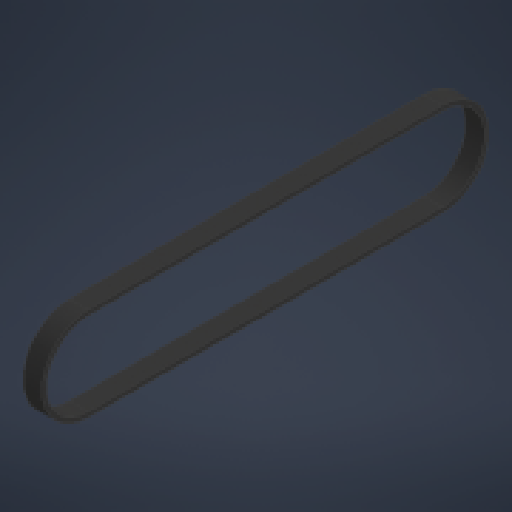
# Autodesk Inventor part: Timing Belt (model only)
Saved by Autodesk Inventor 2026.2 (Build 302298010, 298A)
## iProperties
Created: 2026-05-14
Part Number: Timing Belt (model only)
Material: Generic
Document SubType Name: Modeling
Designer: User
Density: 1 g/cm^3
Appearance: Default
Author: User
Autodesk Inventor part; units mm, degrees
ref_plane "YZ Plane" through (0, 0, 0) normal (1, 0, 0) x (0, 1, 0)
ref_plane "XZ Plane" through (0, 0, 0) normal (0, 1, 0) x (-1, 0, 0)
ref_plane "XY Plane" through (0, 0, 0) normal (0, 0, 1) x (1, 0, 0)
sketch "Sketch1" plane through (0, 0, 0) normal (1, 0, 0) x (0, 1, 0)
  arc A0 (33, 0) -> (-33, 0) centre (0, 0) ccw
  line L0 (33, 0) -> (33, -280)
  line L1 (-33, 0) -> (-33, -280)
  arc A1 (-33, -280) -> (33, -280) centre (0, -280) ccw
  arc A2 (36.81, 0) -> (-36.81, 0) centre (0, 0) ccw
  arc A3 (-36.81, -280) -> (36.81, -280) centre (0, -280) ccw
  line L2 (36.81, 0) -> (36.81, -280)
  line L3 (-36.81, 0) -> (-36.81, -280)
  dimension "d20" = 280
  dimension "d21" = 280
  dimension "d23" = 36.81
  dimension "d24" = 33
  dimension "d25" = 3.81
  dimension "d26" = 280
  dimension "d27" = 280
  constraints: 8 end point, 8 point on circle, 4 centre point, 4 tangent, 3 coincident, 2 vertical
  measures "d20" distance of L0.start L0.end
  measures "d21" distance of L1.start L1.end
  measures "d23" radius of A2
  measures "d24" radius of A0
  measures "d25" distance between parallel lines of L0 L2
  measures "d26" distance of L2.start L2.end
  measures "d27" distance of L3.start L3.end
extrude "Extrusion1" add sketch "Sketch1" along normal blind 15
body "Solid1"
